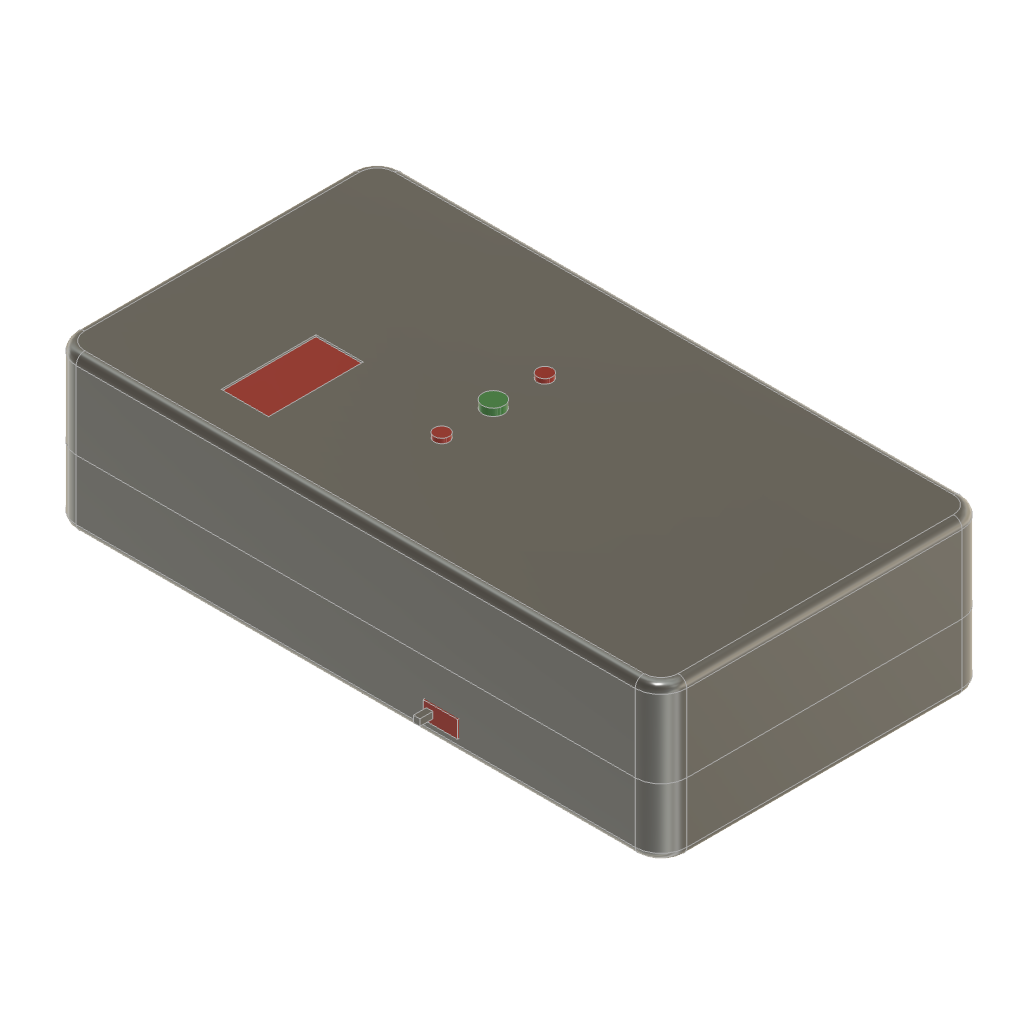
GestureCar_Handheld (Autodesk Fusion 360 design; units mm, degrees)
part number: 2026-11-11-10-58-01-920
part number: 2026-11-11-13-07-00-230
part number: 2026-11-11-13-07-00-249
part number: 2026-11-11-13-07-00-252
part number: 2026-11-11-13-07-00-253
part number: 2026-11-11-13-07-00-255
part number: 2026-11-11-13-07-00-257
part number: 2026-11-11-13-07-00-259
part number: 2026-11-11-13-07-00-261
part number: 2026-11-11-13-07-00-263
part number: 2026-11-11-13-07-00-264
part number: 2026-11-11-13-07-00-266
part number: 2026-11-11-13-07-00-268
part number: 2026-11-11-13-07-00-270
part number: 2026-11-11-13-07-00-272
part number: 2026-11-11-13-07-00-274
part number: 2026-11-11-13-07-00-276
part number: 2026-11-11-13-07-00-278
part number: 2026-11-11-13-07-00-280
Autodesk Fusion 360 part; units mm, degrees
(part 1 of 2)
sketch "Sketch1" plane through (0, 0, 0) normal (0, 0, 1) x (1, 0, 0)
  line L0 (27.5, -14) -> (-27.5, -14)
  line L1 (-27.5, -14) -> (-27.5, 14)
  line L2 (-27.5, 14) -> (27.5, 14)
  line L3 (27.5, 14) -> (27.5, -14)
  line L4 (27.5, -14) -> (-27.5, 14) construction
  line L5 (-27.5, -14) -> (27.5, 14) construction
  dimension "d114" = 55
  dimension "d115" = 28
  constraint horizontal L0
  constraint perpendicular L0 L1
  constraint parallel L0 L2
  constraint parallel L1 L3
  constraint coincident L4 origin
  constraint coincident L5 origin
  measures "d114" distance of L1.end L2.end
  measures "d115" distance of L0.end L1.end
extrude "Extrude1" add sketch "Sketch1" along normal blind 13 makes body 1
sketch "Sketch2" plane through (27.5, 0, 0) normal (1, 0, 0) x (0, 1, 0)
  line L0 (-14, 0) -> (14, 0)
  line L1 (14, 0) -> (14, 13)
  line L2 (14, 13) -> (-14, 13)
  line L3 (-14, 13) -> (-14, 0)
  line L4 (4.5, 11.75) -> (-4.5, 11.75)
  line L5 (-4.5, 11.75) -> (-4.5, 8.25)
  line L6 (-4.5, 8.25) -> (4.5, 8.25)
  line L7 (4.5, 8.25) -> (4.5, 11.75)
  line L8 (4.5, 11.75) -> (-4.5, 8.25) construction
  line L9 (-4.5, 11.75) -> (4.5, 8.25) construction
  point P0 (0, 10)
  dimension "d118" = 9
  dimension "d119" = 3.5
  constraint horizontal L4
  constraint perpendicular L4 L5
  constraint parallel L4 L6
  constraint parallel L5 L7
  constraint coincident L8 P0
  constraint coincident L9 P0
  measures "d118" distance of L5.end L6.end
  measures "d119" distance of L4.end L5.end
extrude "Extrude2" add sketch "Sketch2" along normal blind 2 contours L4 L5 L6 L7 bodies 1
move_body "Move1" bodies 1 to x (1, 0, 0) y (0, 1, 0) z (0, 0, 1) at (0, 0, 1.25)
sketch "Sketch3" plane through (0, 0, 0) normal (0, 0, 1) x (1, 0, 0)
  line L0 (10.5, -8) -> (-10.5, -8)
  line L1 (-10.5, -8) -> (-10.5, 8)
  line L2 (-10.5, 8) -> (10.5, 8)
  line L3 (10.5, 8) -> (10.5, -8)
  line L4 (10.5, -8) -> (-10.5, 8) construction
  line L5 (-10.5, -8) -> (10.5, 8) construction
  dimension "d122" = 21
  dimension "d123" = 16
  constraint horizontal L0
  constraint perpendicular L0 L1
  constraint parallel L0 L2
  constraint parallel L1 L3
  constraint coincident L4 origin
  constraint coincident L5 origin
  measures "d122" distance of L1.end L2.end
  measures "d123" distance of L0.end L1.end
extrude "Extrude3" add sketch "Sketch3" along normal blind 3 separate body makes body 2
sketch "Sketch4" plane through (0, 0, 0) normal (0, 0, 1) x (1, 0, 0)
  line L0 (14, 14) -> (-14, 14)
  line L1 (-14, 14) -> (-14, -14)
  line L2 (-14, -14) -> (14, -14)
  line L3 (14, -14) -> (14, 14)
  line L4 (14, 14) -> (-14, -14) construction
  line L5 (-14, 14) -> (14, -14) construction
  dimension "d126" = 28
  dimension "d127" = 28
  constraint horizontal L0
  constraint perpendicular L0 L1
  constraint parallel L0 L2
  constraint parallel L1 L3
  constraint coincident L4 origin
  constraint coincident L5 origin
  measures "d126" distance of L1.end L2.end
  measures "d127" distance of L0.end L1.end
extrude "Extrude4" add sketch "Sketch4" along normal blind 5 separate body makes body 3
sketch "Sketch5" plane through (0, 0, 5) normal (0, 0, 1) x (-1, 0, 0)
  line L0 (-14, 14) -> (-14, -14)
  line L1 (-14, -14) -> (14, -14)
  line L2 (14, -14) -> (14, 14)
  line L3 (14, 14) -> (-14, 14)
  line L4 (11, 5.5) -> (-11, 5.5)
  line L5 (-11, 5.5) -> (-11, -5.5)
  line L6 (-11, -5.5) -> (11, -5.5)
  line L7 (11, -5.5) -> (11, 5.5)
  line L8 (11, 5.5) -> (-11, -5.5) construction
  line L9 (-11, 5.5) -> (11, -5.5) construction
  dimension "d130" = 22
  dimension "d131" = 11
  constraint horizontal L4
  constraint perpendicular L4 L5
  constraint parallel L4 L6
  constraint parallel L5 L7
  constraint coincident L8 origin
  constraint coincident L9 origin
  measures "d130" distance of L5.end L6.end
  measures "d131" distance of L4.end L5.end
sketch "Sketch6" plane through (0, 0, 0) normal (0, 0, 1) x (1, 0, 0)
  line L0 (3, -3) -> (-3, -3)
  line L1 (-3, -3) -> (-3, 3)
  line L2 (-3, 3) -> (3, 3)
  line L3 (3, 3) -> (3, -3)
  line L4 (3, -3) -> (-3, 3) construction
  line L5 (-3, -3) -> (3, 3) construction
  dimension "d134" = 6
  dimension "d135" = 6
  constraint horizontal L0
  constraint perpendicular L0 L1
  constraint parallel L0 L2
  constraint parallel L1 L3
  constraint coincident L4 origin
  constraint coincident L5 origin
  measures "d134" distance of L1.end L2.end
  measures "d135" distance of L0.end L1.end
extrude "Extrude6" add sketch "Sketch6" along normal blind 5 separate body makes body 4
sketch "Sketch7" plane through (0, 0, 5) normal (0, 0, 1) x (-1, 0, 0)
  line L0 (-3, -3) -> (3, -3)
  line L1 (3, -3) -> (3, 3)
  line L2 (3, 3) -> (-3, 3)
  line L3 (-3, 3) -> (-3, -3)
  circle A0 centre (0, 0) radius 1.75
  dimension "d138" = 3.5
  constraint coincident A0.centre origin
  measures "d138" diameter of A0
extrude "Extrude7" add sketch "Sketch7" along normal blind 1.5 separate body contours A0 makes body 5
sketch "Sketch8" plane through (0, 0, 0) normal (0, 0, 1) x (1, 0, 0)
  line L0 (4, 2) -> (-4, 2)
  line L1 (-4, 2) -> (-4, -2)
  line L2 (-4, -2) -> (4, -2)
  line L3 (4, -2) -> (4, 2)
  line L4 (4, 2) -> (-4, -2) construction
  line L5 (-4, 2) -> (4, -2) construction
  dimension "d141" = 8
  dimension "d142" = 4
  constraint horizontal L0
  constraint perpendicular L0 L1
  constraint parallel L0 L2
  constraint parallel L1 L3
  constraint coincident L4 origin
  constraint coincident L5 origin
  measures "d141" distance of L1.end L2.end
  measures "d142" distance of L0.end L1.end
extrude "Extrude8" add sketch "Sketch8" along normal blind 4 separate body makes body 6
sketch "Sketch9" plane through (0, 0, 4) normal (0, 0, 1) x (-1, 0, 0)
  line L0 (-4, 2) -> (-4, -2)
  line L1 (-4, -2) -> (4, -2)
  line L2 (4, -2) -> (4, 2)
  line L3 (4, 2) -> (-4, 2)
  line L4 (3.25, 0.75) -> (1.75, 0.75)
  line L5 (1.75, 0.75) -> (1.75, -0.75)
  line L6 (1.75, -0.75) -> (3.25, -0.75)
  line L7 (3.25, -0.75) -> (3.25, 0.75)
  line L8 (3.25, 0.75) -> (1.75, -0.75) construction
  line L9 (1.75, 0.75) -> (3.25, -0.75) construction
  point P0 (2.5, 0)
  dimension "d145" = 1.5
  dimension "d146" = 1.5
  constraint horizontal L4
  constraint perpendicular L4 L5
  constraint parallel L4 L6
  constraint parallel L5 L7
  constraint coincident L8 P0
  constraint coincident L9 P0
  measures "d145" distance of L5.end L6.end
  measures "d146" distance of L4.end L5.end
extrude "Extrude9" add sketch "Sketch9" along normal blind 3 separate body contours L4 L5 L6 L7 makes body 7
sketch "Sketch10" plane through (0, 0, 0) normal (0, 0, 1) x (1, 0, 0)
  circle A0 centre (0, 0) radius 2.5
  dimension "d149" = 5
  constraint coincident A0.centre origin
  measures "d149" diameter of A0
extrude "Extrude10" add sketch "Sketch10" along normal blind 8.6 separate body makes body 8
sketch "Sketch11" plane through (0, 0, 0) normal (0, 0, 1) x (1, 0, 0)
  circle A0 centre (0, 0) radius 5
  dimension "d152" = 10
  constraint coincident A0.centre origin
  measures "d152" diameter of A0
extrude "Extrude11" add sketch "Sketch11" along normal blind 3 separate body makes body 9
sketch "Sketch12" plane through (0, 0, 0) normal (0, 0, 1) x (1, 0, 0)
  line L0 (26, 17.5) -> (-26, 17.5)
  line L1 (-26, 17.5) -> (-26, -17.5)
  line L2 (-26, -17.5) -> (26, -17.5)
  line L3 (26, -17.5) -> (26, 17.5)
  line L4 (26, 17.5) -> (-26, -17.5) construction
  line L5 (-26, 17.5) -> (26, -17.5) construction
  dimension "d155" = 52
  dimension "d156" = 35
  constraint horizontal L0
  constraint perpendicular L0 L1
  constraint parallel L0 L2
  constraint parallel L1 L3
  constraint coincident L4 origin
  constraint coincident L5 origin
  measures "d155" distance of L1.end L2.end
  measures "d156" distance of L0.end L1.end
extrude "Extrude12" add sketch "Sketch12" along normal blind 3 separate body makes body 10
sketch "Sketch13" plane through (0, 0, 0) normal (0, 0, 1) x (1, 0, 0)
  line L0 (13, -8.5) -> (-13, -8.5)
  line L1 (-13, -8.5) -> (-13, 8.5)
  line L2 (-13, 8.5) -> (13, 8.5)
  line L3 (13, 8.5) -> (13, -8.5)
  line L4 (13, -8.5) -> (-13, 8.5) construction
  line L5 (-13, -8.5) -> (13, 8.5) construction
  dimension "d159" = 26
  dimension "d160" = 17
  constraint horizontal L0
  constraint perpendicular L0 L1
  constraint parallel L0 L2
  constraint parallel L1 L3
  constraint coincident L4 origin
  constraint coincident L5 origin
  measures "d159" distance of L1.end L2.end
  measures "d160" distance of L0.end L1.end
extrude "Extrude13" add sketch "Sketch13" along normal blind 4 separate body makes body 11
sketch "Sketch14" plane through (0, 0, 0) normal (0, 0, 1) x (1, 0, 0)
  line L0 (20, 10) -> (-20, 10)
  line L1 (-20, 10) -> (-20, -10)
  line L2 (-20, -10) -> (20, -10)
  line L3 (20, -10) -> (20, 10)
  line L4 (20, 10) -> (-20, -10) construction
  line L5 (-20, 10) -> (20, -10) construction
  dimension "d163" = 40
  dimension "d164" = 20
  constraint horizontal L0
  constraint perpendicular L0 L1
  constraint parallel L0 L2
  constraint parallel L1 L3
  constraint coincident L4 origin
  constraint coincident L5 origin
  measures "d163" distance of L1.end L2.end
  measures "d164" distance of L0.end L1.end
extrude "Extrude14" add sketch "Sketch14" along normal blind 12 separate body makes body 12
sketch "Sketch15" plane through (0, 0, 0) normal (0, 0, 1) x (1, 0, 0)
  line L0 (32, 18) -> (-32, 18)
  line L1 (-32, 18) -> (-32, -18)
  line L2 (-32, -18) -> (32, -18)
  line L3 (32, -18) -> (32, 18)
  line L4 (32, 18) -> (-32, -18) construction
  line L5 (-32, 18) -> (32, -18) construction
  dimension "d167" = 64
  dimension "d168" = 36
  constraint horizontal L0
  constraint perpendicular L0 L1
  constraint parallel L0 L2
  constraint parallel L1 L3
  constraint coincident L4 origin
  constraint coincident L5 origin
  measures "d167" distance of L1.end L2.end
  measures "d168" distance of L0.end L1.end
extrude "Extrude15" add sketch "Sketch15" along normal blind 10 separate body makes body 13
sketch "Sketch17" plane through (0, 0, 5) normal (0, 0, 1) x (-1, 0, 0)
  line L0 (-14, 14) -> (-14, -14)
  line L1 (-14, -14) -> (14, -14)
  line L2 (14, -14) -> (14, 14)
  line L3 (14, 14) -> (-14, 14)
  line L4 (30.0905, 17.2402) -> (52.0905, 17.2402)
  line L5 (52.0905, 17.2402) -> (52.0905, 6.2402)
  line L6 (52.0905, 6.2402) -> (30.0905, 6.2402)
  line L7 (30.0905, 6.2402) -> (30.0905, 17.2402)
  line L8 (30.0905, 17.2402) -> (52.0905, 6.2402) construction
  line L9 (52.0905, 17.2402) -> (30.0905, 6.2402) construction
  point P0 (41.0905, 11.7402)
  dimension "d175" = 22
  dimension "d176" = 11
  constraint horizontal L4
  constraint perpendicular L4 L5
  constraint parallel L4 L6
  constraint parallel L5 L7
  constraint coincident L8 P0
  constraint coincident L9 P0
  measures "d175" distance of L5.end L6.end
  measures "d176" distance of L4.end L5.end
copy_body "CopyPasteBodies1" bodies 5 4 makes body 14 makes body 15
move_body "Move16" bodies 1 to x (1, 0, 0) y (0, 1, 0) z (0, 0, 1) at (-40.5, 17, 19.6)
move_body "Move17" bodies 3 to x (1, 0, 0) y (0, 1, 0) z (0, 0, 1) at (-40.5, -17, 28.6)
move_body "Move18" bodies 2 to x (1, 0, 0) y (0, 1, 0) z (0, 0, 1) at (30, 24, 29.6)
move_body "Move19" bodies 13 to x (1, 0, 0) y (0, 1, 0) z (0, 0, 1) at (35, -8, 22.6)
move_body "Move20" bodies 4 5 to x (1, 0, 0) y (0, 1, 0) z (0, 0, 1) at (-6, 12, 25.6)
move_body "Move21" bodies 14 15 to x (1, 0, 0) y (0, 1, 0) z (0, 0, 1) at (-6, -12, 25.6)
move_body "Move22" bodies 8 to x (1, 0, 0) y (0, 1, 0) z (0, 0, 1) at (-6, 0, 27.1)
move_body "Move23" bodies 10 to x (1, 0, 0) y (0, 1, 0) z (0, 0, 1) at (-34, 0, 2.4)
move_body "Move24" bodies 12 to x (1, 0, 0) y (0, 1, 0) z (0, 0, 1) at (20, -18, 2.4)
move_body "Move25" bodies 11 to x (1, 0, 0) y (0, 1, 0) z (0, 0, 1) at (17, 22, 3.4)
move_body "Move26" bodies 6 7 to x (1, 0, 0) y (0, 0, 1) z (0, -1, 0) at (20, -35.3, 5.4)
move_body "Move27" bodies 9 to x (1, 0, 0) y (0, 1, 0) z (0, 0, 1) at (55, 0, 2.4)
move_body "Move28" bodies 1 to x (-1, 0, 0) y (0, -1, 0) z (0, 0, 1) at (-81, 34, 0)
sketch "Sketch18" plane through (0, 0, 33.6) normal (0, 0, 1) x (-1, 0, 0)
  line L0 (26.5, 31) -> (26.5, 3)
  line L1 (26.5, 3) -> (54.5, 3)
  line L2 (54.5, 3) -> (54.5, 31)
  line L3 (54.5, 31) -> (26.5, 31)
  line L4 (43.3445, 25.904) -> (32.3445, 25.904)
  line L5 (32.3445, 25.904) -> (32.3445, 3.904)
  line L6 (32.3445, 3.904) -> (43.3445, 3.904)
  line L7 (43.3445, 3.904) -> (43.3445, 25.904)
  line L8 (43.3445, 25.904) -> (32.3445, 3.904) construction
  line L9 (32.3445, 25.904) -> (43.3445, 3.904) construction
  point P0 (37.8445, 14.904)
  dimension "d179" = 11
  dimension "d180" = 22
  constraint horizontal L4
  constraint perpendicular L4 L5
  constraint parallel L4 L6
  constraint parallel L5 L7
  constraint coincident L8 P0
  constraint coincident L9 P0
  measures "d179" distance of L5.end L6.end
  measures "d180" distance of L4.end L5.end
extrude "Extrude18" add sketch "Sketch18" along normal blind 2 separate body contours L4 L5 L6 L7 makes body 16
move_body "Move29" bodies 16 to x (1, 0, 0) y (0, 1, 0) z (0, 0, 1) at (2, -2, 0)
sketch "Sketch19" plane through (0, 0, 0) normal (0, 0, 1) x (1, 0, 0)
  line L0 (65, 38) -> (-65, 38)
  line L1 (-71, 32) -> (-71, -32)
  line L2 (-65, -38) -> (65, -38)
  line L3 (71, -32) -> (71, 32)
  line L4 (71, 38) -> (-71, -38) construction
  line L5 (-71, 38) -> (71, -38) construction
  arc A0 (-65, 38) -> (-71, 32) centre (-65, 32) ccw
  arc A1 (-71, -32) -> (-65, -38) centre (-65, -32) ccw
  arc A2 (71, 32) -> (65, 38) centre (65, 32) ccw
  arc A3 (65, -38) -> (71, -32) centre (65, -32) ccw
  dimension "d183" = 142
  dimension "d184" = 76
  dimension "d185" = 6
  constraint horizontal L0
  constraint perpendicular L0 L1
  constraint parallel L0 L2
  constraint parallel L1 L3
  constraint coincident L4 origin
  constraint coincident L5 origin
  constraint coincident L5.start L0
  constraint coincident L5.start L1
  constraint tangent L0 A0
  constraint tangent L1 A0
  constraint coincident L4.end L1
  constraint coincident L4.end L2
  constraint tangent L1 A1
  constraint tangent L2 A1
  constraint equal A0 A1
  constraint coincident L4.start L0
  constraint coincident L4.start L3
  constraint tangent L0 A2
  constraint tangent L3 A2
  constraint equal A0 A2
  constraint coincident L5.end L3
  constraint coincident L5.end L2
  constraint tangent L3 A3
  constraint tangent L2 A3
  constraint equal A0 A3
  measures "d183" distance of L4.end L5.end
  measures "d184" distance of L5.start L4.end
  measures "d185" radius of A0
extrude "Extrude19" add sketch "Sketch19" along normal blind 36 separate body makes body 17
fillet "Fillet1" radius 2 16 edges at (71, 0, 36) (69.2426, 36.2426, 36) (0, 38, 36) (-69.2426, 36.2426, 36) (-71, 0, 36) (-69.2426, -36.2426, 36) (0, -38, 36) (69.2426, -36.2426, 36) (71, 0, 0) (69.2426, 36.2426, 0) (0, 38, 0) (-69.2426, 36.2426, 0) (-71, 0, 0) (-69.2426, -36.2426, 0) (0, -38, 0) (69.2426, -36.2426, 0) on bodies 17
ref_plane "WorkPlane1" through (0, 0, 16) normal (0, 0, 1) x (1, 0, 0)
split "Split1" by plane through (0, 0, 16) normal (0, 0, 1) bodies 17 makes body 18 at (-21.6667, -12, 36)
copy_body "Body->Comp1" bodies 1 removing the originals makes body 19 in component "D_esp32"
copy_body "Body->Comp2" bodies 2 removing the originals makes body 20 in component "D_imu"
copy_body "Body->Comp3" bodies 3 removing the originals makes body 21 in component "D_oled_board"
copy_body "Body->Comp4" bodies 4 removing the originals makes body 22 in component "D_btn(arm)"
copy_body "Body->Comp5" bodies 5 removing the originals makes body 23 in component "D_btn_poke(arm)"
copy_body "Body->Comp6" bodies 6 removing the originals makes body 24 in component "D_switch_body"
copy_body "Body->Comp7" bodies 7 removing the originals makes body 25 in component "D_switch_lever"
copy_body "Body->Comp8" bodies 8 removing the originals makes body 26 in component "D_rgb"
copy_body "Body->Comp9" bodies 9 removing the originals makes body 27 in component "D_vib"
copy_body "Body->Comp10" bodies 10 removing the originals makes body 28 in component "D_lipo"
copy_body "Body->Comp11" bodies 11 removing the originals makes body 29 in component "D_tp4056"
copy_body "Body->Comp12" bodies 12 removing the originals makes body 30 in component "D_boost"
copy_body "Body->Comp13" bodies 13 removing the originals makes body 31 in component "D_tag"
copy_body "Body->Comp14" bodies 14 removing the originals makes body 32 in component "D_btn_poke (mode)"
copy_body "Body->Comp15" bodies 15 removing the originals makes body 33 in component "D_btn (mode)"
copy_body "Body->Comp16" bodies 16 removing the originals makes body 34 in component "D_oled_screen"
copy_body "Body->Comp17" bodies 17 removing the originals makes body 35 in component "COVER"
copy_body "Body->Comp18" bodies 18 removing the originals makes body 36 in component "SHELL"
shell "Shell1" thickness 2.4 removed faces 1 at (21.6667, -12.6667, 16) on bodies 36 in component "SHELL"
sketch "Sketch20" plane through (0, 0, 28.6) normal (0, 0, -1) x (1, 0, 0)
  line L0 (-26.5, 3) -> (-26.5, 31)
  line L1 (-26.5, 31) -> (-54.5, 31)
  line L2 (-54.5, 31) -> (-54.5, 3)
  line L3 (-54.5, 3) -> (-26.5, 3)
  line L4 (-54.5, 3) -> (-54.5, 31)
  line L5 (-54.5, 31) -> (-26.5, 31)
  line L6 (-26.5, 3) -> (-54.5, 3)
  line L7 (-26.5, 31) -> (-26.5, 3)
  line L8 (-54.8, 2.7) -> (-26.2, 2.7)
  line L9 (-26.2, 2.7) -> (-26.2, 31.3)
  line L10 (-26.2, 31.3) -> (-54.8, 31.3)
  line L11 (-54.8, 31.3) -> (-54.8, 2.7)
  line L12 (-56.4, 1.1) -> (-24.6, 1.1)
  line L13 (-24.6, 1.1) -> (-24.6, 32.9)
  line L14 (-24.6, 32.9) -> (-56.4, 32.9)
  line L15 (-56.4, 32.9) -> (-56.4, 1.1)
  dimension "d193" = 0.3
  dimension "d194" = 1.6
extrude "Extrude1'" add sketch "Sketch20" against normal blind 5 contours L12 L13 L14 L15 bodies 36 in component "SHELL"
move_body "Move1'" bodies 19 to x (1, 0, 0) y (0, 1, 0) z (0, 0, 1) at (-0.6, 0, 0) in component "D_esp32"
sketch "Sketch21" plane through (0, 0, 33.6) normal (0, 0, -1) x (1, 0, 0)
  line L0 (-68.6, 32) -> (-68.6, -32)
  arc A0 (-68.6, -32) -> (-65, -35.6) centre (-65, -32) ccw
  line L1 (-65, -35.6) -> (65, -35.6)
  arc A1 (65, -35.6) -> (68.6, -32) centre (65, -32) ccw
  line L2 (68.6, -32) -> (68.6, 32)
  arc A2 (68.6, 32) -> (65, 35.6) centre (65, 32) ccw
  line L3 (65, 35.6) -> (-65, 35.6)
  arc A3 (-65, 35.6) -> (-68.6, 32) centre (-65, 32) ccw
  line L4 (-24.6, 1.1) -> (-56.4, 1.1)
  line L5 (-56.4, 1.1) -> (-56.4, 32.9)
  line L6 (-56.4, 32.9) -> (-24.6, 32.9)
  line L7 (-24.6, 32.9) -> (-24.6, 1.1)
  line L8 (-13.6, -3) -> (-68.6, -3)
  line L9 (-13.6, -31) -> (-13.6, -3)
  line L10 (-68.6, -31) -> (-13.6, -31)
  line L11 (-68.6, -31.3) -> (-13.3, -31.3)
  line L12 (-13.3, -31.3) -> (-13.3, -2.7)
  line L13 (-13.3, -2.7) -> (-68.6, -2.7)
  line L14 (-68.6, -32.9) -> (-11.7, -32.9)
  line L15 (-11.7, -32.9) -> (-11.7, -1.1)
  line L16 (-11.7, -1.1) -> (-68.6, -1.1)
  dimension "d197" = 0.3
  dimension "d198" = 1.6
extrude "Extrude2'" add sketch "Sketch21" along normal blind 6.5 contours L0 A0 L11 L12 L13 L14 L15 L16 bodies 36 in component "SHELL"
sketch "Sketch22" plane through (0, 0, 33.6) normal (0, 0, -1) x (1, 0, 0)
  line L0 (-24.6, 1.1) -> (-56.4, 1.1)
  line L1 (-56.4, 1.1) -> (-56.4, 32.9)
  line L2 (-56.4, 32.9) -> (-24.6, 32.9)
  line L3 (-24.6, 32.9) -> (-24.6, 1.1)
  line L4 (-68.6, -1.1) -> (-11.7, -1.1)
  line L5 (-11.7, -1.1) -> (-11.7, -32.9)
  line L6 (-11.7, -32.9) -> (-68.4857, -32.9)
  arc A0 (-68.4857, -32.9) -> (-65, -35.6) centre (-65, -32) ccw
  line L7 (-65, -35.6) -> (65, -35.6)
  arc A1 (65, -35.6) -> (68.6, -32) centre (65, -32) ccw
  line L8 (68.6, -32) -> (68.6, 32)
  arc A2 (68.6, 32) -> (65, 35.6) centre (65, 32) ccw
  line L9 (65, 35.6) -> (-65, 35.6)
  arc A3 (-65, 35.6) -> (-68.6, 32) centre (-65, 32) ccw
  line L10 (-68.6, 32) -> (-68.6, -1.1)
  line L11 (40.5, -16) -> (19.5, -16)
  line L12 (40.5, -32) -> (40.5, -16)
  line L13 (19.5, -16) -> (19.5, -32)
  line L14 (19.5, -32) -> (40.5, -32)
  line L15 (19.2, -32.3) -> (40.8, -32.3)
  line L16 (40.8, -32.3) -> (40.8, -15.7)
  line L17 (40.8, -15.7) -> (19.2, -15.7)
  line L18 (19.2, -15.7) -> (19.2, -32.3)
  line L19 (17.6, -33.9) -> (42.4, -33.9)
  line L20 (42.4, -33.9) -> (42.4, -14.1)
  line L21 (42.4, -14.1) -> (17.6, -14.1)
  line L22 (17.6, -14.1) -> (17.6, -33.9)
  dimension "d201" = 0.3
  dimension "d202" = 1.6
extrude "Extrude3'" add sketch "Sketch22" along normal blind 4 contours L19 L20 L21 L22 bodies 36 in component "SHELL"
move_body "Move1''" bodies 31 to x (1, 0, 0) y (0, 1, 0) z (0, 0, 1) at (1.6, 0, 0) in component "D_tag"
sketch "Sketch24" plane through (0, 0, 33.6) normal (0, 0, -1) x (1, 0, 0)
  line L0 (-68.6, -1.1) -> (-11.7, -1.1)
  line L1 (-11.7, -1.1) -> (-11.7, -32.9)
  line L2 (-11.7, -32.9) -> (-68.4857, -32.9)
  arc A0 (-68.4857, -32.9) -> (-65, -35.6) centre (-65, -32) ccw
  line L3 (-65, -35.6) -> (65, -35.6)
  arc A1 (65, -35.6) -> (68.6, -32) centre (65, -32) ccw
  line L4 (68.6, -32) -> (68.6, 32)
  arc A2 (68.6, 32) -> (65, 35.6) centre (65, 32) ccw
  line L5 (65, 35.6) -> (-65, 35.6)
  arc A3 (-65, 35.6) -> (-68.6, 32) centre (-65, 32) ccw
  line L6 (-68.6, 32) -> (-68.6, -1.1)
  line L7 (-24.6, 1.1) -> (-56.4, 1.1)
  line L8 (-56.4, 1.1) -> (-56.4, 32.9)
  line L9 (-56.4, 32.9) -> (-24.6, 32.9)
  line L10 (-24.6, 32.9) -> (-24.6, 1.1)
  line L11 (17.6, -14.1) -> (42.4, -14.1)
  line L12 (42.4, -14.1) -> (42.4, -33.9)
  line L13 (42.4, -33.9) -> (17.6, -33.9)
  line L14 (17.6, -33.9) -> (17.6, -14.1)
  line L15 (4.6, 26) -> (68.6, 26)
  line L16 (4.6, -10) -> (4.6, 26)
  line L17 (68.6, -10) -> (4.6, -10)
  line L18 (68.6, -10.3) -> (4.3, -10.3)
  line L19 (4.3, -10.3) -> (4.3, 26.3)
  line L20 (4.3, 26.3) -> (68.6, 26.3)
  line L21 (68.6, -11.9) -> (2.7, -11.9)
  line L22 (2.7, -11.9) -> (2.7, 27.9)
  line L23 (2.7, 27.9) -> (68.6, 27.9)
extrude "Extrude4'" add sketch "Sketch24" along normal blind 5 contours L4 L18 L19 L20 L21 L22 L23 bodies 36 in component "SHELL"
sketch "Sketch25" plane through (0, 0, 33.6) normal (0, 0, -1) x (1, 0, 0)
  line L0 (2.7, 27.9) -> (68.6, 27.9)
  line L1 (68.6, 27.9) -> (68.6, 32)
  arc A0 (68.6, 32) -> (65, 35.6) centre (65, 32) ccw
  line L2 (65, 35.6) -> (-65, 35.6)
  arc A1 (-65, 35.6) -> (-68.6, 32) centre (-65, 32) ccw
  line L3 (-68.6, 32) -> (-68.6, -1.1)
  line L4 (-68.6, -1.1) -> (-11.7, -1.1)
  line L5 (-11.7, -1.1) -> (-11.7, -32.9)
  line L6 (-11.7, -32.9) -> (-68.4857, -32.9)
  arc A2 (-68.4857, -32.9) -> (-65, -35.6) centre (-65, -32) ccw
  line L7 (-65, -35.6) -> (65, -35.6)
  arc A3 (65, -35.6) -> (68.6, -32) centre (65, -32) ccw
  line L8 (68.6, -32) -> (68.6, -11.9)
  line L9 (68.6, -11.9) -> (2.7, -11.9)
  line L10 (2.7, -11.9) -> (2.7, 27.9)
  line L11 (-24.6, 1.1) -> (-56.4, 1.1)
  line L12 (-56.4, 1.1) -> (-56.4, 32.9)
  line L13 (-56.4, 32.9) -> (-24.6, 32.9)
  line L14 (-24.6, 32.9) -> (-24.6, 1.1)
  line L15 (17.6, -14.1) -> (42.4, -14.1)
  line L16 (42.4, -14.1) -> (42.4, -33.9)
  line L17 (42.4, -33.9) -> (17.6, -33.9)
  line L18 (17.6, -33.9) -> (17.6, -14.1)
  circle A4 centre (-6, 0) radius 2.5
  circle A5 centre (-6, 0) radius 2.8
  circle A6 centre (-6, 0) radius 4.4
  dimension "d209" = 0.3
  dimension "d210" = 1.6
extrude "Extrude5" add sketch "Sketch25" along normal blind 4.3 contours A6 bodies 36 in component "SHELL"
sketch "Sketch26" plane through (-70.6, 0, 0) normal (-1, 0, 0) x (0, -1, 0)
  line L0 (-12.5, 29.1) -> (-12.5, 32.6)
  line L1 (-12.5, 32.6) -> (-21.5, 32.6)
  line L2 (-21.5, 32.6) -> (-21.5, 29.1)
  line L3 (-21.5, 29.1) -> (-12.5, 29.1)
  line L4 (-12.5, 32.6) -> (-21.5, 32.6)
  line L5 (-21.5, 32.6) -> (-21.5, 29.1)
  line L6 (-21.5, 29.1) -> (-12.5, 29.1)
  line L7 (-12.5, 29.1) -> (-12.5, 32.6)
extrude "Extrude6'" cut sketch "Sketch26" along normal blind 3 bodies 36 in component "SHELL"
extrude "Extrude1''" cut 1 faces at (-70.6, 18.5, 31.4333) along direction (1, 0, 0) blind 2 on bodies 19 bodies 19 in component "D_esp32"
extrude "Extrude7'" cut 1 faces at (-70.6, 18.5, 31.4333) along direction (1, 0, 0) blind 2 on bodies 36 bodies 36 in component "SHELL"
sketch "Sketch27" plane through (-68.6, 0, 0) normal (-1, 0, 0) x (0, -1, 0)
  line L0 (-31, 20.85) -> (-3, 20.85)
  line L1 (-3, 20.85) -> (-3, 33.85)
  line L2 (-3, 33.85) -> (-31, 33.85)
  line L3 (-31, 33.85) -> (-31, 20.85)
  line L4 (-21.5, 32.6) -> (-12.5, 32.6)
  line L5 (-21.5, 29.1) -> (-21.5, 32.6)
  line L6 (-12.5, 29.1) -> (-21.5, 29.1)
  line L7 (-12.5, 32.6) -> (-12.5, 29.1)
extrude "Extrude2''" add sketch "Sketch27" along normal blind 2 contours L4 L5 L6 L7 bodies 19 in component "D_esp32"
sketch "Sketch28" plane through (0, 0, 28.6) normal (0, 0, -1) x (1, 0, 0)
  line L0 (-54.8, 2.7) -> (-54.8, 31.3)
  line L1 (-54.8, 31.3) -> (-26.2, 31.3)
  line L2 (-26.2, 31.3) -> (-26.2, 2.7)
  line L3 (-26.2, 2.7) -> (-54.8, 2.7)
  line L4 (-56.4, 32.9) -> (-56.4, 1.1)
  line L5 (-56.4, 1.1) -> (-24.6, 1.1)
  line L6 (-24.6, 1.1) -> (-24.6, 32.9)
  line L7 (-24.6, 32.9) -> (-56.4, 32.9)
  line L8 (-54.7191, 22) -> (-56.5039, 22)
  line L9 (-56.5039, 22) -> (-56.5039, 12)
  line L10 (-56.5039, 12) -> (-54.7191, 12)
  line L11 (-54.7191, 12) -> (-54.7191, 22)
  line L12 (-54.7191, 22) -> (-56.5039, 12) construction
  line L13 (-56.5039, 22) -> (-54.7191, 12) construction
  point P0 (-55.6115, 17)
  dimension "d221" = 10
  constraint horizontal L8
  constraint perpendicular L8 L9
  constraint parallel L8 L10
  constraint parallel L9 L11
  constraint coincident L12 P0
  constraint coincident L13 P0
  measures "d221" distance of L8.end L9.end
extrude "Extrude8'" cut sketch "Sketch28" against normal blind 5 contours L0 L4 L8 L10 bodies 36 in component "SHELL"
sketch "Sketch29" plane through (0, 0, 29.6) normal (0, 0, -1) x (1, 0, 0)
  line L0 (19.2, -32.3) -> (19.2, -15.7)
  line L1 (19.2, -15.7) -> (40.8, -15.7)
  line L2 (40.8, -15.7) -> (40.8, -32.3)
  line L3 (40.8, -32.3) -> (19.2, -32.3)
  line L4 (17.6, -14.1) -> (17.6, -33.9)
  line L5 (17.6, -33.9) -> (42.4, -33.9)
  line L6 (42.4, -33.9) -> (42.4, -14.1)
  line L7 (42.4, -14.1) -> (17.6, -14.1)
  line L8 (40.6566, -21) -> (44.1434, -21)
  line L9 (44.1434, -21) -> (44.1434, -27)
  line L10 (44.1434, -27) -> (40.6566, -27)
  line L11 (40.6566, -27) -> (40.6566, -21)
  line L12 (40.6566, -21) -> (44.1434, -27) construction
  line L13 (44.1434, -21) -> (40.6566, -27) construction
  point P0 (42.4, -24)
  dimension "d224" = 6
  constraint horizontal L8
  constraint perpendicular L8 L9
  constraint parallel L8 L10
  constraint parallel L9 L11
  constraint coincident L12 P0
  constraint coincident L13 P0
  constraint midpoint L6 P0
  measures "d224" distance of L8.end L9.end
extrude "Extrude9'" cut sketch "Sketch29" against normal blind 4 contours L2 L6 L8 L10 bodies 36 in component "SHELL"
sketch "Sketch30" plane through (0, 0, 27.1) normal (0, 0, -1) x (1, 0, 0)
  line L0 (-68.6, -31.3) -> (-68.6, -32)
  arc A0 (-68.6, -32) -> (-68.4857, -32.9) centre (-65, -32) ccw
  line L1 (-68.4857, -32.9) -> (-11.7, -32.9)
  line L2 (-11.7, -32.9) -> (-11.7, -1.1)
  line L3 (-11.7, -1.1) -> (-68.6, -1.1)
  line L4 (-68.6, -1.1) -> (-68.6, -2.7)
  line L5 (-68.6, -2.7) -> (-13.3, -2.7)
  line L6 (-13.3, -2.7) -> (-13.3, -31.3)
  line L7 (-13.3, -31.3) -> (-68.6, -31.3)
  line L8 (-35, -2.7916) -> (-45, -2.7916)
  line L9 (-45, -2.7916) -> (-45, -1.0084)
  line L10 (-45, -1.0084) -> (-35, -1.0084)
  line L11 (-35, -1.0084) -> (-35, -2.7916)
  line L12 (-35, -2.7916) -> (-45, -1.0084) construction
  line L13 (-45, -2.7916) -> (-35, -1.0084) construction
  line L14 (-35, -33.0026) -> (-45, -33.0026)
  line L15 (-45, -33.0026) -> (-45, -31.1745)
  line L16 (-45, -31.1745) -> (-35, -31.1745)
  line L17 (-35, -31.1745) -> (-35, -33.0026)
  line L18 (-35, -33.0026) -> (-45, -31.1745) construction
  line L19 (-45, -33.0026) -> (-35, -31.1745) construction
  point P0 (-40, -1.9)
  point P1 (-40, -32.0885)
  dimension "d227" = 10
  dimension "d228" = 10
  constraint horizontal L8
  constraint perpendicular L8 L9
  constraint parallel L8 L10
  constraint parallel L9 L11
  constraint coincident L12 P0
  constraint coincident L13 P0
  constraint horizontal L14
  constraint perpendicular L14 L15
  constraint parallel L14 L16
  constraint parallel L15 L17
  constraint coincident L18 P1
  constraint coincident L19 P1
  measures "d227" distance of L9.end L10.end
  measures "d228" distance of L15.end L16.end
extrude "Extrude10'" cut sketch "Sketch30" against normal blind 6.5 contours L1 L7 L15 L17 | L3 L5 L9 L11 | L3 L9 L10 L11 bodies 36 in component "SHELL"
sketch "Sketch31" plane through (0, 0, 28.6) normal (0, 0, -1) x (1, 0, 0)
  line L0 (68.6, -11.9) -> (68.6, -10.3)
  line L1 (68.6, -10.3) -> (4.3, -10.3)
  line L2 (4.3, -10.3) -> (4.3, 26.3)
  line L3 (4.3, 26.3) -> (68.6, 26.3)
  line L4 (68.6, 26.3) -> (68.6, 27.9)
  line L5 (68.6, 27.9) -> (2.7, 27.9)
  line L6 (2.7, 27.9) -> (2.7, -11.9)
  line L7 (2.7, -11.9) -> (68.6, -11.9)
  line L8 (40.0177, -10.1229) -> (30.0177, -10.1229)
  line L9 (30.0177, -10.1229) -> (30.0177, -12.2172)
  line L10 (30.0177, -12.2172) -> (40.0177, -12.2172)
  line L11 (40.0177, -12.2172) -> (40.0177, -10.1229)
  line L12 (40.0177, -10.1229) -> (30.0177, -12.2172) construction
  line L13 (30.0177, -10.1229) -> (40.0177, -12.2172) construction
  line L14 (40.0177, 28.0937) -> (30.0177, 28.0937)
  line L15 (30.0177, 28.0937) -> (30.0177, 26.1088)
  line L16 (30.0177, 26.1088) -> (40.0177, 26.1088)
  line L17 (40.0177, 26.1088) -> (40.0177, 28.0937)
  line L18 (40.0177, 28.0937) -> (30.0177, 26.1088) construction
  line L19 (30.0177, 28.0937) -> (40.0177, 26.1088) construction
  point P0 (35.0177, -11.1701)
  point P1 (35.0177, 27.1013)
  dimension "d231" = 10
  dimension "d232" = 10
  constraint horizontal L8
  constraint perpendicular L8 L9
  constraint parallel L8 L10
  constraint parallel L9 L11
  constraint coincident L12 P0
  constraint coincident L13 P0
  constraint horizontal L14
  constraint perpendicular L14 L15
  constraint parallel L14 L16
  constraint parallel L15 L17
  constraint coincident L18 P1
  constraint coincident L19 P1
  measures "d231" distance of L9.end L10.end
  measures "d232" distance of L15.end L16.end
extrude "Extrude11'" cut sketch "Sketch31" against normal blind 5 contours L1 L7 L9 L11 | L3 L5 L15 L17 bodies 36 in component "SHELL"
sketch "Sketch32" plane through (0, 0, 33.6) normal (0, 0, -1) x (1, 0, 0)
  line L0 (40.0177, -10.3) -> (68.6, -10.3)
  line L1 (68.6, -10.3) -> (68.6, 26.3)
  line L2 (68.6, 26.3) -> (40.0177, 26.3)
  line L3 (40.0177, 26.3) -> (40.0177, 27.9)
  line L4 (40.0177, 27.9) -> (68.6, 27.9)
  line L5 (68.6, 27.9) -> (68.6, 32)
  arc A0 (68.6, 32) -> (65, 35.6) centre (65, 32) ccw
  line L6 (65, 35.6) -> (-65, 35.6)
  arc A1 (-65, 35.6) -> (-68.6, 32) centre (-65, 32) ccw
  line L7 (-68.6, 32) -> (-68.6, -1.1)
  line L8 (-68.6, -1.1) -> (-45, -1.1)
  line L9 (-45, -1.1) -> (-45, -2.7)
  line L10 (-45, -2.7) -> (-68.6, -2.7)
  line L11 (-68.6, -2.7) -> (-68.6, -31.3)
  line L12 (-68.6, -31.3) -> (-45, -31.3)
  line L13 (-45, -31.3) -> (-45, -32.9)
  line L14 (-45, -32.9) -> (-68.4857, -32.9)
  arc A2 (-68.4857, -32.9) -> (-65, -35.6) centre (-65, -32) ccw
  line L15 (-65, -35.6) -> (65, -35.6)
  arc A3 (65, -35.6) -> (68.6, -32) centre (65, -32) ccw
  line L16 (68.6, -32) -> (68.6, -11.9)
  line L17 (68.6, -11.9) -> (40.0177, -11.9)
  line L18 (40.0177, -11.9) -> (40.0177, -10.3)
  line L19 (-35, -31.3) -> (-13.3, -31.3)
  line L20 (-13.3, -31.3) -> (-13.3, -2.7)
  line L21 (-13.3, -2.7) -> (-35, -2.7)
  line L22 (-35, -2.7) -> (-35, -1.1)
  line L23 (-35, -1.1) -> (-11.7, -1.1)
  line L24 (-11.7, -1.1) -> (-11.7, -32.9)
  line L25 (-11.7, -32.9) -> (-35, -32.9)
  line L26 (-35, -32.9) -> (-35, -31.3)
  line L27 (-26.2, 31.3) -> (-54.8, 31.3)
  line L28 (-54.8, 31.3) -> (-54.8, 22)
  line L29 (-54.8, 22) -> (-56.4, 22)
  line L30 (-56.4, 22) -> (-56.4, 32.9)
  line L31 (-56.4, 32.9) -> (-24.6, 32.9)
  line L32 (-24.6, 32.9) -> (-24.6, 1.1)
  line L33 (-24.6, 1.1) -> (-56.4, 1.1)
  line L34 (-56.4, 1.1) -> (-56.4, 12)
  line L35 (-56.4, 12) -> (-54.8, 12)
  line L36 (-54.8, 12) -> (-54.8, 2.7)
  line L37 (-54.8, 2.7) -> (-26.2, 2.7)
  line L38 (-26.2, 2.7) -> (-26.2, 31.3)
  line L39 (17.6, -14.1) -> (42.4, -14.1)
  line L40 (42.4, -14.1) -> (42.4, -21)
  line L41 (42.4, -21) -> (40.8, -21)
  line L42 (40.8, -21) -> (40.8, -15.7)
  line L43 (40.8, -15.7) -> (19.2, -15.7)
  line L44 (19.2, -15.7) -> (19.2, -32.3)
  line L45 (19.2, -32.3) -> (40.8, -32.3)
  line L46 (40.8, -32.3) -> (40.8, -27)
  line L47 (40.8, -27) -> (42.4, -27)
  line L48 (42.4, -27) -> (42.4, -33.9)
  line L49 (42.4, -33.9) -> (17.6, -33.9)
  line L50 (17.6, -33.9) -> (17.6, -14.1)
  circle A4 centre (-6, 0) radius 4.4
  line L51 (30.0177, -10.3) -> (30.0177, -11.9)
  line L52 (30.0177, -11.9) -> (2.7, -11.9)
  line L53 (2.7, -11.9) -> (2.7, 27.9)
  line L54 (2.7, 27.9) -> (30.0177, 27.9)
  line L55 (30.0177, 27.9) -> (30.0177, 26.3)
  line L56 (30.0177, 26.3) -> (4.3, 26.3)
  line L57 (4.3, 26.3) -> (4.3, -10.3)
  line L58 (4.3, -10.3) -> (30.0177, -10.3)
  circle A5 centre (-6, -12) radius 4.7
  circle A6 centre (-6, -12) radius 5.45
  circle A7 centre (-6, 12) radius 4.7
  circle A8 centre (-6, 12) radius 5.45
  dimension "d235" = 9.4
  dimension "d236" = 10.9
  dimension "d237" = 9.4
  dimension "d238" = 10.9
  constraint concentric A5 A6
  constraint concentric A7 A8
  measures "d235" diameter of A5
  measures "d236" diameter of A6
  measures "d237" diameter of A7
  measures "d238" diameter of A8
extrude "Extrude12'" add sketch "Sketch32" along normal blind 8 contours A6 | A8 bodies 36 in component "SHELL"
sketch "Sketch33" plane through (0, 0, 33.6) normal (0, 0, -1) x (1, 0, 0)
  circle A0 centre (-6, -12) radius 5.45
  line L0 (40.0177, -10.3) -> (68.6, -10.3)
  line L1 (68.6, -10.3) -> (68.6, 26.3)
  line L2 (68.6, 26.3) -> (40.0177, 26.3)
  line L3 (40.0177, 26.3) -> (40.0177, 27.9)
  line L4 (40.0177, 27.9) -> (68.6, 27.9)
  line L5 (68.6, 27.9) -> (68.6, 32)
  arc A1 (68.6, 32) -> (65, 35.6) centre (65, 32) ccw
  line L6 (65, 35.6) -> (-65, 35.6)
  arc A2 (-65, 35.6) -> (-68.6, 32) centre (-65, 32) ccw
  line L7 (-68.6, 32) -> (-68.6, -1.1)
  line L8 (-68.6, -1.1) -> (-45, -1.1)
  line L9 (-45, -1.1) -> (-45, -2.7)
  line L10 (-45, -2.7) -> (-68.6, -2.7)
  line L11 (-68.6, -2.7) -> (-68.6, -31.3)
  line L12 (-68.6, -31.3) -> (-45, -31.3)
  line L13 (-45, -31.3) -> (-45, -32.9)
  line L14 (-45, -32.9) -> (-68.4857, -32.9)
  arc A3 (-68.4857, -32.9) -> (-65, -35.6) centre (-65, -32) ccw
  line L15 (-65, -35.6) -> (65, -35.6)
  arc A4 (65, -35.6) -> (68.6, -32) centre (65, -32) ccw
  line L16 (68.6, -32) -> (68.6, -11.9)
  line L17 (68.6, -11.9) -> (40.0177, -11.9)
  line L18 (40.0177, -11.9) -> (40.0177, -10.3)
  line L19 (-35, -31.3) -> (-13.3, -31.3)
  line L20 (-13.3, -31.3) -> (-13.3, -2.7)
  line L21 (-13.3, -2.7) -> (-35, -2.7)
  line L22 (-35, -2.7) -> (-35, -1.1)
  line L23 (-35, -1.1) -> (-11.7, -1.1)
  line L24 (-11.7, -1.1) -> (-11.7, -32.9)
  line L25 (-11.7, -32.9) -> (-35, -32.9)
  line L26 (-35, -32.9) -> (-35, -31.3)
  line L27 (-26.2, 31.3) -> (-54.8, 31.3)
  line L28 (-54.8, 31.3) -> (-54.8, 22)
  line L29 (-54.8, 22) -> (-56.4, 22)
  line L30 (-56.4, 22) -> (-56.4, 32.9)
  line L31 (-56.4, 32.9) -> (-24.6, 32.9)
  line L32 (-24.6, 32.9) -> (-24.6, 1.1)
  line L33 (-24.6, 1.1) -> (-56.4, 1.1)
  line L34 (-56.4, 1.1) -> (-56.4, 12)
  line L35 (-56.4, 12) -> (-54.8, 12)
  line L36 (-54.8, 12) -> (-54.8, 2.7)
  line L37 (-54.8, 2.7) -> (-26.2, 2.7)
  line L38 (-26.2, 2.7) -> (-26.2, 31.3)
  line L39 (17.6, -14.1) -> (42.4, -14.1)
  line L40 (42.4, -14.1) -> (42.4, -21)
  line L41 (42.4, -21) -> (40.8, -21)
  line L42 (40.8, -21) -> (40.8, -15.7)
  line L43 (40.8, -15.7) -> (19.2, -15.7)
  line L44 (19.2, -15.7) -> (19.2, -32.3)
  line L45 (19.2, -32.3) -> (40.8, -32.3)
  line L46 (40.8, -32.3) -> (40.8, -27)
  line L47 (40.8, -27) -> (42.4, -27)
  line L48 (42.4, -27) -> (42.4, -33.9)
  line L49 (42.4, -33.9) -> (17.6, -33.9)
  line L50 (17.6, -33.9) -> (17.6, -14.1)
  circle A5 centre (-6, 0) radius 4.4
  line L51 (30.0177, -10.3) -> (30.0177, -11.9)
  line L52 (30.0177, -11.9) -> (2.7, -11.9)
  line L53 (2.7, -11.9) -> (2.7, 27.9)
  line L54 (2.7, 27.9) -> (30.0177, 27.9)
  line L55 (30.0177, 27.9) -> (30.0177, 26.3)
  line L56 (30.0177, 26.3) -> (4.3, 26.3)
  line L57 (4.3, 26.3) -> (4.3, -10.3)
  line L58 (4.3, -10.3) -> (30.0177, -10.3)
  circle A6 centre (-6, 12) radius 5.45
  circle A7 centre (8, -31) radius 2.5
  circle A8 centre (63, -31) radius 2.5
  circle A9 centre (8, 31) radius 2.5
  circle A10 centre (63, 31) radius 2.5
  dimension "d241" = 5
  dimension "d242" = 5
  dimension "d243" = 5
  dimension "d244" = 5
  measures "d241" diameter of A7
  measures "d242" diameter of A8
  measures "d243" diameter of A9
  measures "d244" diameter of A10
extrude "Extrude13'" add sketch "Sketch33" along normal blind 17.6 contours A7 | A8 | A9 | A10 bodies 36 in component "SHELL"
sketch "Sketch34" plane through (0, 0, 16) normal (0, 0, -1) x (1, 0, 0)
  circle A0 centre (63, -31) radius 2.5
  circle A1 centre (63, -31) radius 1.5
  circle A2 centre (8, -31) radius 1.5
  circle A3 centre (8, 31) radius 1.5
  circle A4 centre (63, 31) radius 1.5
  dimension "d247" = 3
  dimension "d248" = 3
  dimension "d249" = 3
  dimension "d250" = 3
  constraint concentric A0 A1
  measures "d247" diameter of A1
  measures "d248" diameter of A2
  measures "d249" diameter of A3
  measures "d250" diameter of A4
extrude "Extrude14'" cut sketch "Sketch34" against normal blind 5 contours A1 | A2 | A3 | A4 bodies 36 in component "SHELL"
extrude "Extrude15'" cut 1 faces at (-34.0111, -20.5707, 35.6) along direction (0, 0, 1) mid plane 10 on bodies 34 bodies 36 in component "SHELL"
extrude "Extrude16" cut 1 faces at (-6.1795, -12.4733, 32.1) along direction (0, 0, 1) mid plane 10 on bodies 32 bodies 36 in component "SHELL"
extrude "Extrude17" cut 1 faces at (-6.1795, 11.5267, 32.1) along direction (0, 0, 1) mid plane 28 on bodies 23 bodies 36 in component "SHELL"
extrude "Extrude18'" cut 1 faces at (-6.8863, 0.2321, 35.7) along direction (0, 0, 1) blind 12 on bodies 26 bodies 36 in component "SHELL"
shell "Shell1'" thickness 2.4 removed faces 1 at (21.6667, -12.6667, 16) on bodies 35 in component "COVER"
sketch "Sketch35" plane through (0, 0, 2.4) normal (0, 0, 1) x (-1, 0, 0)
  arc A0 (65, -35.6) -> (68.6, -32) centre (65, -32) ccw
  line L0 (68.6, -32) -> (68.6, 32)
  arc A1 (68.6, 32) -> (65, 35.6) centre (65, 32) ccw
  line L1 (65, 35.6) -> (-65, 35.6)
  arc A2 (-65, 35.6) -> (-68.6, 32) centre (-65, 32) ccw
  line L2 (-68.6, 32) -> (-68.6, -32)
  arc A3 (-68.6, -32) -> (-65, -35.6) centre (-65, -32) ccw
  line L3 (-65, -35.6) -> (65, -35.6)
  circle A4 centre (8, -31) radius 2.5
  circle A5 centre (63, -31) radius 2.5
  circle A6 centre (8, 31) radius 2.5
  circle A7 centre (63, 31) radius 2.5
  dimension "d262" = 5
  dimension "d263" = 5
  dimension "d264" = 5
  dimension "d265" = 5
  measures "d262" diameter of A4
  measures "d263" diameter of A5
  measures "d264" diameter of A6
  measures "d265" diameter of A7
extrude "Extrude1'''" add sketch "Sketch35" along normal up to surface (13.6 mm away) contours A4 | A5 | A6 | A7 bodies 35 in component "COVER"
sketch "Sketch36" plane through (0, 0, 0) normal (0, 0, -1) x (1, 0, 0)
  line L0 (69, -32) -> (69, 32)
  arc A0 (69, 32) -> (65, 36) centre (65, 32) ccw
  line L1 (65, 36) -> (-65, 36)
  arc A1 (-65, 36) -> (-69, 32) centre (-65, 32) ccw
  line L2 (-69, 32) -> (-69, -32)
  arc A2 (-69, -32) -> (-65, -36) centre (-65, -32) ccw
  line L3 (-65, -36) -> (65, -36)
  arc A3 (65, -36) -> (69, -32) centre (65, -32) ccw
  circle A4 centre (-8, 31) radius 1.3
  circle A5 centre (-63, 31) radius 1.3
  circle A6 centre (-8, -31) radius 1.3
  circle A7 centre (-63, -31) radius 1.3
  dimension "d268" = 2.6
  dimension "d269" = 2.6
  dimension "d270" = 2.6
  dimension "d271" = 2.6
  measures "d268" diameter of A4
  measures "d269" diameter of A5
  measures "d270" diameter of A6
  measures "d271" diameter of A7
extrude "Extrude2'''" cut sketch "Sketch36" against normal up to surface (16 mm away) contours A4 | A5 | A6 | A7 bodies 35 in component "COVER"
sketch "Sketch37" plane through (0, 0, 0) normal (0, 0, -1) x (1, 0, 0)
  circle A0 centre (-8, 31) radius 1.3
  circle A1 centre (-63, -31) radius 1.3
  circle A2 centre (-63, 31) radius 1.3
  circle A3 centre (-8, -31) radius 1.3
  line L0 (69, -32) -> (69, 32)
  arc A4 (69, 32) -> (65, 36) centre (65, 32) ccw
  line L1 (65, 36) -> (-65, 36)
  arc A5 (-65, 36) -> (-69, 32) centre (-65, 32) ccw
  line L2 (-69, 32) -> (-69, -32)
  arc A6 (-69, -32) -> (-65, -36) centre (-65, -32) ccw
  line L3 (-65, -36) -> (65, -36)
  arc A7 (65, -36) -> (69, -32) centre (65, -32) ccw
  circle A8 centre (-63, 31) radius 2.3
  circle A9 centre (-8, 31) radius 2.3
  circle A10 centre (-63, -31) radius 2.3
  circle A11 centre (-8, -31) radius 2.3
  dimension "d274" = 4.6
  dimension "d275" = 4.6
  dimension "d276" = 4.6
  dimension "d277" = 4.6
  constraint concentric A2 A8
  constraint concentric A0 A9
  constraint concentric A1 A10
  constraint concentric A3 A11
  measures "d274" diameter of A8
  measures "d275" diameter of A9
  measures "d276" diameter of A10
  measures "d277" diameter of A11
extrude "Extrude3''" cut sketch "Sketch37" against normal blind 1.6 contours A8 | A9 | A10 | A11 bodies 35 in component "COVER"
sketch "Sketch38" plane through (0, 0, 2.4) normal (0, 0, 1) x (-1, 0, 0)
  circle A0 centre (8, -31) radius 2.5
  circle A1 centre (63, 31) radius 2.5
  circle A2 centre (63, -31) radius 2.5
  circle A3 centre (8, 31) radius 2.5
  arc A4 (65, -35.6) -> (68.6, -32) centre (65, -32) ccw
  line L0 (68.6, -32) -> (68.6, 32)
  arc A5 (68.6, 32) -> (65, 35.6) centre (65, 32) ccw
  line L1 (65, 35.6) -> (-65, 35.6)
  arc A6 (-65, 35.6) -> (-68.6, 32) centre (-65, 32) ccw
  line L2 (-68.6, 32) -> (-68.6, -32)
  arc A7 (-68.6, -32) -> (-65, -35.6) centre (-65, -32) ccw
  line L3 (-65, -35.6) -> (65, -35.6)
  line L4 (8, -17.5) -> (60, -17.5)
  line L5 (60, -17.5) -> (60, 17.5)
  line L6 (60, 17.5) -> (8, 17.5)
  line L7 (8, 17.5) -> (8, -17.5)
  line L8 (60.3, -17.8) -> (60.3, 17.8)
  line L9 (60.3, 17.8) -> (7.7, 17.8)
  line L10 (7.7, 17.8) -> (7.7, -17.8)
  line L11 (7.7, -17.8) -> (60.3, -17.8)
  line L12 (61.9, -19.4) -> (61.9, 19.4)
  line L13 (61.9, 19.4) -> (6.1, 19.4)
  line L14 (6.1, 19.4) -> (6.1, -19.4)
  line L15 (6.1, -19.4) -> (61.9, -19.4)
  dimension "d280" = 0.3
  dimension "d281" = 1.6
extrude "Extrude4''" add sketch "Sketch38" along normal blind 1.5 contours L12 L13 L14 L15 bodies 35 in component "COVER"
sketch "Sketch40" plane through (0, 0, 2.4) normal (0, 0, 1) x (-1, 0, 0)
  line L0 (6.1, -19.4) -> (6.1, 19.4)
  line L1 (6.1, 19.4) -> (61.9, 19.4)
  line L2 (61.9, 19.4) -> (61.9, -19.4)
  line L3 (61.9, -19.4) -> (6.1, -19.4)
  circle A0 centre (8, -31) radius 2.5
  circle A1 centre (63, 31) radius 2.5
  circle A2 centre (63, -31) radius 2.5
  circle A3 centre (8, 31) radius 2.5
  arc A4 (65, -35.6) -> (68.6, -32) centre (65, -32) ccw
  line L4 (68.6, -32) -> (68.6, 32)
  arc A5 (68.6, 32) -> (65, 35.6) centre (65, 32) ccw
  line L5 (65, 35.6) -> (-65, 35.6)
  arc A6 (-65, 35.6) -> (-68.6, 32) centre (-65, 32) ccw
  line L6 (-68.6, 32) -> (-68.6, -32)
  arc A7 (-68.6, -32) -> (-65, -35.6) centre (-65, -32) ccw
  line L7 (-65, -35.6) -> (65, -35.6)
  line L8 (-40, 8) -> (0, 8)
  line L9 (0, 8) -> (0, 28)
  line L10 (0, 28) -> (-40, 28)
  line L11 (-40, 28) -> (-40, 8)
  line L12 (0.3, 7.7) -> (0.3, 28.3)
  line L13 (0.3, 28.3) -> (-40.3, 28.3)
  line L14 (-40.3, 28.3) -> (-40.3, 7.7)
  line L15 (-40.3, 7.7) -> (0.3, 7.7)
  line L16 (1.9, 6.1) -> (1.9, 29.9)
  line L17 (1.9, 29.9) -> (-41.9, 29.9)
  line L18 (-41.9, 29.9) -> (-41.9, 6.1)
  line L19 (-41.9, 6.1) -> (1.9, 6.1)
  dimension "d288" = 0.3
  dimension "d289" = 1.6
extrude "Extrude6''" add sketch "Sketch40" along normal blind 6 contours L16 L17 L18 L19 bodies 35 in component "COVER"
sketch "Sketch41" plane through (0, 0, 2.4) normal (0, 0, 1) x (-1, 0, 0)
  arc A0 (65, -35.6) -> (68.6, -32) centre (65, -32) ccw
  line L0 (68.6, -32) -> (68.6, 32)
  arc A1 (68.6, 32) -> (65, 35.6) centre (65, 32) ccw
  line L1 (65, 35.6) -> (-65, 35.6)
  arc A2 (-65, 35.6) -> (-68.6, 32) centre (-65, 32) ccw
  line L2 (-68.6, 32) -> (-68.6, -32)
  arc A3 (-68.6, -32) -> (-65, -35.6) centre (-65, -32) ccw
  line L3 (-65, -35.6) -> (65, -35.6)
  circle A4 centre (8, 31) radius 2.5
  circle A5 centre (63, -31) radius 2.5
  circle A6 centre (63, 31) radius 2.5
  circle A7 centre (8, -31) radius 2.5
  line L4 (6.1, -19.4) -> (6.1, 19.4)
  line L5 (6.1, 19.4) -> (61.9, 19.4)
  line L6 (61.9, 19.4) -> (61.9, -19.4)
  line L7 (61.9, -19.4) -> (6.1, -19.4)
  line L8 (-41.9, 6.1) -> (-41.9, 29.9)
  line L9 (-41.9, 29.9) -> (1.9, 29.9)
  line L10 (1.9, 29.9) -> (1.9, 6.1)
  line L11 (1.9, 6.1) -> (-41.9, 6.1)
  circle A8 centre (-55, 0) radius 5
  circle A9 centre (-55, 0) radius 5.3
  circle A10 centre (-55, 0) radius 6.9
  dimension "d292" = 0.3
  dimension "d293" = 1.6
extrude "Extrude7''" add sketch "Sketch41" along normal blind 3 contours A10 bodies 35 in component "COVER"
move_body "Move1'''" bodies 29 to x (0, 1, 0) y (-1, 0, 0) z (0, 0, 1) at (43.1201, 5.6634, 0) in component "D_tp4056"
sketch "Sketch42" plane through (0, 0, 2.4) normal (0, 0, 1) x (-1, 0, 0)
  line L0 (-41.9, 6.1) -> (-41.9, 29.9)
  line L1 (-41.9, 29.9) -> (1.9, 29.9)
  line L2 (1.9, 29.9) -> (1.9, 6.1)
  line L3 (1.9, 6.1) -> (-41.9, 6.1)
  arc A0 (65, -35.6) -> (68.6, -32) centre (65, -32) ccw
  line L4 (68.6, -32) -> (68.6, 32)
  arc A1 (68.6, 32) -> (65, 35.6) centre (65, 32) ccw
  line L5 (65, 35.6) -> (-65, 35.6)
  arc A2 (-65, 35.6) -> (-68.6, 32) centre (-65, 32) ccw
  line L6 (-68.6, 32) -> (-68.6, -32)
  arc A3 (-68.6, -32) -> (-65, -35.6) centre (-65, -32) ccw
  line L7 (-65, -35.6) -> (65, -35.6)
  circle A4 centre (8, 31) radius 2.5
  circle A5 centre (63, -31) radius 2.5
  circle A6 centre (63, 31) radius 2.5
  circle A7 centre (8, -31) radius 2.5
  line L8 (6.1, -19.4) -> (6.1, 19.4)
  line L9 (6.1, 19.4) -> (61.9, 19.4)
  line L10 (61.9, 19.4) -> (61.9, -19.4)
  line L11 (61.9, -19.4) -> (6.1, -19.4)
  circle A8 centre (-55, 0) radius 6.9
  line L12 (-12.6201, -35.6634) -> (-12.6201, -9.6634)
  line L13 (-29.6201, -9.6634) -> (-29.6201, -35.6634)
  line L14 (-12.6201, -9.6634) -> (-29.6201, -9.6634)
  line L15 (-12.3201, -35.6634) -> (-12.3201, -9.3634)
  line L16 (-12.3201, -9.3634) -> (-29.9201, -9.3634)
  line L17 (-29.9201, -9.3634) -> (-29.9201, -35.6634)
  line L18 (-10.7201, -35.6634) -> (-10.7201, -7.7634)
  line L19 (-10.7201, -7.7634) -> (-31.5201, -7.7634)
  line L20 (-31.5201, -7.7634) -> (-31.5201, -35.6634)
  dimension "d296" = 0.3
  dimension "d297" = 1.6
extrude "Extrude8''" add sketch "Sketch42" along normal blind 5 contours L7 L15 L16 L17 L18 L19 L20 bodies 35 in component "COVER"
sketch "Sketch43" plane through (0, 35.6634, 0) normal (0, 1, 0) x (-1, 0, 0)
  line L0 (-29.6201, 3.4) -> (-12.6201, 3.4)
  line L1 (-12.6201, 3.4) -> (-12.6201, 7.4)
  line L2 (-12.6201, 7.4) -> (-29.6201, 7.4)
  line L3 (-29.6201, 7.4) -> (-29.6201, 3.4)
  line L4 (-14.5, 10.5) -> (-27.5, 10.5)
  line L5 (-27.5, 10.5) -> (-27.5, 3.5)
  line L6 (-27.5, 3.5) -> (-14.5, 3.5)
  line L7 (-14.5, 3.5) -> (-14.5, 10.5)
  line L8 (-14.5, 10.5) -> (-27.5, 3.5) construction
  line L9 (-27.5, 10.5) -> (-14.5, 3.5) construction
  point P0 (-21, 7)
  dimension "d300" = 13
  dimension "d301" = 7
  constraint horizontal L4
  constraint perpendicular L4 L5
  constraint parallel L4 L6
  constraint parallel L5 L7
  constraint coincident L8 P0
  constraint coincident L9 P0
  measures "d300" distance of L5.end L6.end
  measures "d301" distance of L4.end L5.end
extrude "Extrude9''" cut sketch "Sketch43" along normal blind 12 contours L2 L4 L5 L7 | L2 L5 L6 L7 bodies 35 in component "COVER"
extrude "Extrude10''" cut 1 faces at (23.1667, 35.6634, 5.8333) along direction (0, -1, 0) blind 7 on bodies 35 bodies 35 in component "COVER"
component "D_esp32" placed x (1, 0, 0) y (0, 1, 0) z (0, 0, 1) at (0, 0, 0)
component "D_imu" placed x (1, 0, 0) y (0, 1, 0) z (0, 0, 1) at (0, 0, 0)
component "D_oled_board" placed x (1, 0, 0) y (0, 1, 0) z (0, 0, 1) at (0, 0, 0)
component "D_btn(arm)" placed x (1, 0, 0) y (0, 1, 0) z (0, 0, 1) at (0, 0, 5)
component "D_btn_poke(arm)" placed x (1, 0, 0) y (0, 1, 0) z (0, 0, 1) at (0, 0, 5)
component "D_switch_body" placed x (1, 0, 0) y (0, 1, 0) z (0, 0, 1) at (0, 1, 0)
component "D_switch_lever" placed x (1, 0, 0) y (0, 1, 0) z (0, 0, 1) at (0, 1, 0)
component "D_rgb" placed x (1, 0, 0) y (0, 1, 0) z (0, 0, 1) at (0, 0, 2)
component "D_vib" placed x (1, 0, 0) y (0, 1, 0) z (0, 0, 1) at (0, 0, 0)
component "D_lipo" placed x (1, 0, 0) y (0, 1, 0) z (0, 0, 1) at (0, 0, 0)